Autodesk Fusion 360 part; units mm, degrees
(part 21 of 28)
  line L4025 (139.1545, 85.638) -> (139.2932, 85.4993)
  line L4026 (139.2932, 85.4993) -> (139.4085, 85.3407)
  line L4027 (139.4085, 85.3407) -> (139.4975, 85.1659)
  line L4028 (139.4975, 85.1659) -> (139.5582, 84.9793)
  line L4029 (139.5582, 84.9793) -> (139.5888, 84.7856)
  line L4030 (139.5888, 84.7856) -> (139.5927, 84.6875)
  line L4031 (139.5927, 84.6875) -> (139.5927, 84.1875)
  line L4032 (139.5927, 84.1875) -> (139.5888, 84.0895)
  line L4033 (139.5888, 84.0895) -> (139.5582, 83.8957)
  line L4034 (139.5582, 83.8957) -> (139.4975, 83.7092)
  line L4035 (139.4975, 83.7092) -> (139.4085, 83.5344)
  line L4036 (139.4085, 83.5344) -> (139.2932, 83.3757)
  line L4037 (139.2932, 83.3757) -> (139.1545, 83.237)
  line L4038 (139.1545, 83.237) -> (138.9958, 83.1217)
  line L4039 (138.9958, 83.1217) -> (138.821, 83.0327)
  line L4040 (138.821, 83.0327) -> (138.6345, 82.9721)
  line L4041 (138.6345, 82.9721) -> (138.4408, 82.9414)
  line L4042 (138.4408, 82.9414) -> (138.2446, 82.9414)
  line L4043 (138.2446, 82.9414) -> (138.0509, 82.9721)
  line L4044 (138.0509, 82.9721) -> (137.8643, 83.0327)
  line L4045 (137.8643, 83.0327) -> (137.6896, 83.1217)
  line L4046 (137.6896, 83.1217) -> (137.5309, 83.237)
  line L4047 (137.5309, 83.237) -> (137.3922, 83.3757)
  line L4048 (137.3922, 83.3757) -> (137.2769, 83.5344)
  line L4049 (137.2769, 83.5344) -> (137.1878, 83.7092)
  line L4050 (137.1878, 83.7092) -> (137.1272, 83.8957)
  line L4051 (137.1272, 83.8957) -> (137.0965, 84.0895)
  line L4052 (137.0965, 84.0895) -> (137.0927, 84.1875)
  line L4053 (137.0927, 84.1875) -> (137.0927, 84.6875)
  line L4054 (137.0927, 84.6875) -> (137.0965, 84.7856)
  line L4055 (137.0965, 84.7856) -> (137.1272, 84.9793)
  line L4056 (137.1272, 84.9793) -> (137.1878, 85.1659)
  line L4057 (137.1878, 85.1659) -> (137.2769, 85.3407)
  line L4058 (137.2769, 85.3407) -> (137.3922, 85.4993)
  line L4059 (137.3922, 85.4993) -> (137.5309, 85.638)
  line L4060 (137.5309, 85.638) -> (137.6896, 85.7533)
  line L4061 (137.6896, 85.7533) -> (137.8643, 85.8424)
  line L4062 (137.8643, 85.8424) -> (138.0509, 85.903)
  line L4063 (138.0509, 85.903) -> (138.2446, 85.9337)
  line L4064 (138.2446, 85.9337) -> (138.4408, 85.9337)
  line L4065 (138.4408, 85.9337) -> (138.6345, 85.903)
  line L4066 (24.7524, 89.0733) -> (22.3024, 89.0733)
  line L4067 (22.3024, 89.0733) -> (22.3024, 92.0733)
  line L4068 (22.3024, 92.0733) -> (24.7524, 92.0733)
  line L4069 (24.7524, 92.0733) -> (24.7524, 89.0733)
  line L4070 (59.6774, 89.0733) -> (57.2274, 89.0733)
  line L4071 (57.2274, 89.0733) -> (57.2274, 92.0733)
  line L4072 (57.2274, 92.0733) -> (59.6774, 92.0733)
  line L4073 (59.6774, 92.0733) -> (59.6774, 89.0733)
  line L4074 (94.6024, 89.0733) -> (92.1524, 89.0733)
  line L4075 (92.1524, 89.0733) -> (92.1524, 92.0733)
  line L4076 (92.1524, 92.0733) -> (94.6024, 92.0733)
  line L4077 (94.6024, 92.0733) -> (94.6024, 89.0733)
  line L4078 (129.5274, 89.0733) -> (127.0774, 89.0733)
  line L4079 (127.0774, 89.0733) -> (127.0774, 92.0733)
  line L4080 (127.0774, 92.0733) -> (129.5274, 92.0733)
  line L4081 (129.5274, 92.0733) -> (129.5274, 89.0733)
  line L4082 (21.2733, 92.0395) -> (21.4562, 91.9801)
  line L4083 (21.4562, 91.9801) -> (21.6274, 91.8928)
  line L4084 (21.6274, 91.8928) -> (21.7829, 91.7798)
  line L4085 (21.7829, 91.7798) -> (21.9189, 91.6439)
  line L4086 (21.9189, 91.6439) -> (22.0319, 91.4884)
  line L4087 (22.0319, 91.4884) -> (22.1191, 91.3171)
  line L4088 (22.1191, 91.3171) -> (22.1785, 91.1343)
  line L4089 (22.1785, 91.1343) -> (22.2086, 90.9444)
  line L4090 (22.2086, 90.9444) -> (22.2124, 90.8483)
  line L4091 (22.2124, 90.8483) -> (22.2124, 90.2983)
  line L4092 (22.2124, 90.2983) -> (22.2086, 90.2022)
  line L4093 (22.2086, 90.2022) -> (22.1785, 90.0123)
  line L4094 (22.1785, 90.0123) -> (22.1191, 89.8295)
  line L4095 (22.1191, 89.8295) -> (22.0319, 89.6583)
  line L4096 (22.0319, 89.6583) -> (21.9189, 89.5027)
  line L4097 (21.9189, 89.5027) -> (21.7829, 89.3668)
  line L4098 (21.7829, 89.3668) -> (21.6274, 89.2538)
  line L4099 (21.6274, 89.2538) -> (21.4562, 89.1666)
  line L4100 (21.4562, 89.1666) -> (21.2733, 89.1072)
  line L4101 (21.2733, 89.1072) -> (21.0835, 89.0771)
  line L4102 (21.0835, 89.0771) -> (20.8913, 89.0771)
  line L4103 (20.8913, 89.0771) -> (20.7014, 89.1072)
  line L4104 (20.7014, 89.1072) -> (20.5186, 89.1666)
  line L4105 (20.5186, 89.1666) -> (20.3473, 89.2538)
  line L4106 (20.3473, 89.2538) -> (20.1918, 89.3668)
  line L4107 (20.1918, 89.3668) -> (20.0559, 89.5027)
  line L4108 (20.0559, 89.5027) -> (19.9429, 89.6583)
  line L4109 (19.9429, 89.6583) -> (19.8556, 89.8295)
  line L4110 (19.8556, 89.8295) -> (19.7962, 90.0123)
  line L4111 (19.7962, 90.0123) -> (19.7661, 90.2022)
  line L4112 (19.7661, 90.2022) -> (19.7624, 90.2983)
  line L4113 (19.7624, 90.2983) -> (19.7624, 90.8483)
  line L4114 (19.7624, 90.8483) -> (19.7661, 90.9444)
  line L4115 (19.7661, 90.9444) -> (19.7962, 91.1343)
  line L4116 (19.7962, 91.1343) -> (19.8556, 91.3171)
  line L4117 (19.8556, 91.3171) -> (19.9429, 91.4884)
  line L4118 (19.9429, 91.4884) -> (20.0559, 91.6439)
  line L4119 (20.0559, 91.6439) -> (20.1918, 91.7798)
  line L4120 (20.1918, 91.7798) -> (20.3473, 91.8928)
  line L4121 (20.3473, 91.8928) -> (20.5186, 91.9801)
  line L4122 (20.5186, 91.9801) -> (20.7014, 92.0395)
  line L4123 (20.7014, 92.0395) -> (20.8913, 92.0695)
  line L4124 (20.8913, 92.0695) -> (21.0835, 92.0695)
  line L4125 (21.0835, 92.0695) -> (21.2733, 92.0395)
  line L4126 (56.1983, 92.0395) -> (56.3812, 91.9801)
  line L4127 (56.3812, 91.9801) -> (56.5524, 91.8928)
  line L4128 (56.5524, 91.8928) -> (56.7079, 91.7798)
  line L4129 (56.7079, 91.7798) -> (56.8439, 91.6439)
  line L4130 (56.8439, 91.6439) -> (56.9569, 91.4884)
  line L4131 (56.9569, 91.4884) -> (57.0441, 91.3171)
  line L4132 (57.0441, 91.3171) -> (57.1035, 91.1343)
  line L4133 (57.1035, 91.1343) -> (57.1336, 90.9444)
  line L4134 (57.1336, 90.9444) -> (57.1374, 90.8483)
  line L4135 (57.1374, 90.8483) -> (57.1374, 90.2983)
  line L4136 (57.1374, 90.2983) -> (57.1336, 90.2022)
  line L4137 (57.1336, 90.2022) -> (57.1035, 90.0123)
  line L4138 (57.1035, 90.0123) -> (57.0441, 89.8295)
  line L4139 (57.0441, 89.8295) -> (56.9569, 89.6583)
  line L4140 (56.9569, 89.6583) -> (56.8439, 89.5027)
  line L4141 (56.8439, 89.5027) -> (56.7079, 89.3668)
  line L4142 (56.7079, 89.3668) -> (56.5524, 89.2538)
  line L4143 (56.5524, 89.2538) -> (56.3812, 89.1666)
  line L4144 (56.3812, 89.1666) -> (56.1983, 89.1072)
  line L4145 (56.1983, 89.1072) -> (56.0085, 89.0771)
  line L4146 (56.0085, 89.0771) -> (55.8163, 89.0771)
  line L4147 (55.8163, 89.0771) -> (55.6264, 89.1072)
  line L4148 (55.6264, 89.1072) -> (55.4436, 89.1666)
  line L4149 (55.4436, 89.1666) -> (55.2723, 89.2538)
  line L4150 (55.2723, 89.2538) -> (55.1168, 89.3668)
  line L4151 (55.1168, 89.3668) -> (54.9809, 89.5027)
  line L4152 (54.9809, 89.5027) -> (54.8679, 89.6583)
  line L4153 (54.8679, 89.6583) -> (54.7806, 89.8295)
  line L4154 (54.7806, 89.8295) -> (54.7212, 90.0123)
  line L4155 (54.7212, 90.0123) -> (54.6911, 90.2022)
  line L4156 (54.6911, 90.2022) -> (54.6874, 90.2983)
  line L4157 (54.6874, 90.2983) -> (54.6874, 90.8483)
  line L4158 (54.6874, 90.8483) -> (54.6911, 90.9444)
  line L4159 (54.6911, 90.9444) -> (54.7212, 91.1343)
  line L4160 (54.7212, 91.1343) -> (54.7806, 91.3171)
  line L4161 (54.7806, 91.3171) -> (54.8679, 91.4884)
  line L4162 (54.8679, 91.4884) -> (54.9809, 91.6439)
  line L4163 (54.9809, 91.6439) -> (55.1168, 91.7798)
  line L4164 (55.1168, 91.7798) -> (55.2723, 91.8928)
  line L4165 (55.2723, 91.8928) -> (55.4436, 91.9801)
  line L4166 (55.4436, 91.9801) -> (55.6264, 92.0395)
  line L4167 (55.6264, 92.0395) -> (55.8163, 92.0695)
  line L4168 (55.8163, 92.0695) -> (56.0085, 92.0695)
  line L4169 (56.0085, 92.0695) -> (56.1983, 92.0395)
  line L4170 (91.1233, 92.0395) -> (91.3062, 91.9801)
  line L4171 (91.3062, 91.9801) -> (91.4774, 91.8928)
  line L4172 (91.4774, 91.8928) -> (91.6329, 91.7798)
  line L4173 (91.6329, 91.7798) -> (91.7689, 91.6439)
  line L4174 (91.7689, 91.6439) -> (91.8819, 91.4884)
  line L4175 (91.8819, 91.4884) -> (91.9691, 91.3171)
  line L4176 (91.9691, 91.3171) -> (92.0285, 91.1343)
  line L4177 (92.0285, 91.1343) -> (92.0586, 90.9444)
  line L4178 (92.0586, 90.9444) -> (92.0624, 90.8483)
  line L4179 (92.0624, 90.8483) -> (92.0624, 90.2983)
  line L4180 (92.0624, 90.2983) -> (92.0586, 90.2022)
  line L4181 (92.0586, 90.2022) -> (92.0285, 90.0123)
  line L4182 (92.0285, 90.0123) -> (91.9691, 89.8295)
  line L4183 (91.9691, 89.8295) -> (91.8819, 89.6583)
  line L4184 (91.8819, 89.6583) -> (91.7689, 89.5027)
  line L4185 (91.7689, 89.5027) -> (91.6329, 89.3668)
  line L4186 (91.6329, 89.3668) -> (91.4774, 89.2538)
  line L4187 (91.4774, 89.2538) -> (91.3062, 89.1666)
  line L4188 (91.3062, 89.1666) -> (91.1233, 89.1072)
  line L4189 (91.1233, 89.1072) -> (90.9335, 89.0771)
  line L4190 (90.9335, 89.0771) -> (90.7413, 89.0771)
  line L4191 (90.7413, 89.0771) -> (90.5514, 89.1072)
  line L4192 (90.5514, 89.1072) -> (90.3686, 89.1666)
  line L4193 (90.3686, 89.1666) -> (90.1973, 89.2538)
  line L4194 (90.1973, 89.2538) -> (90.0418, 89.3668)
  line L4195 (90.0418, 89.3668) -> (89.9059, 89.5027)
  line L4196 (89.9059, 89.5027) -> (89.7929, 89.6583)
  line L4197 (89.7929, 89.6583) -> (89.7056, 89.8295)
  line L4198 (89.7056, 89.8295) -> (89.6462, 90.0123)
  line L4199 (89.6462, 90.0123) -> (89.6161, 90.2022)
  line L4200 (89.6161, 90.2022) -> (89.6124, 90.2983)
  line L4201 (89.6124, 90.2983) -> (89.6124, 90.8483)
  line L4202 (89.6124, 90.8483) -> (89.6161, 90.9444)
  line L4203 (89.6161, 90.9444) -> (89.6462, 91.1343)
  line L4204 (89.6462, 91.1343) -> (89.7056, 91.3171)
  line L4205 (89.7056, 91.3171) -> (89.7929, 91.4884)
  line L4206 (89.7929, 91.4884) -> (89.9059, 91.6439)
  line L4207 (89.9059, 91.6439) -> (90.0418, 91.7798)
  line L4208 (90.0418, 91.7798) -> (90.1973, 91.8928)
  line L4209 (90.1973, 91.8928) -> (90.3686, 91.9801)
  line L4210 (90.3686, 91.9801) -> (90.5514, 92.0395)
  line L4211 (90.5514, 92.0395) -> (90.7413, 92.0695)
  line L4212 (90.7413, 92.0695) -> (90.9335, 92.0695)
  line L4213 (90.9335, 92.0695) -> (91.1233, 92.0395)
  line L4214 (126.0483, 92.0395) -> (126.2312, 91.9801)
  line L4215 (126.2312, 91.9801) -> (126.4024, 91.8928)
  line L4216 (126.4024, 91.8928) -> (126.5579, 91.7798)
  line L4217 (126.5579, 91.7798) -> (126.6939, 91.6439)
  line L4218 (126.6939, 91.6439) -> (126.8069, 91.4884)
  line L4219 (126.8069, 91.4884) -> (126.8941, 91.3171)
  line L4220 (126.8941, 91.3171) -> (126.9535, 91.1343)
  line L4221 (126.9535, 91.1343) -> (126.9836, 90.9444)
  line L4222 (126.9836, 90.9444) -> (126.9874, 90.8483)
  line L4223 (126.9874, 90.8483) -> (126.9874, 90.2983)
  line L4224 (126.9874, 90.2983) -> (126.9836, 90.2022)
  line L4225 (126.9836, 90.2022) -> (126.9535, 90.0123)
  line L4226 (126.9535, 90.0123) -> (126.8941, 89.8295)
  line L4227 (126.8941, 89.8295) -> (126.8069, 89.6583)
  line L4228 (126.8069, 89.6583) -> (126.6939, 89.5027)
  line L4229 (126.6939, 89.5027) -> (126.5579, 89.3668)
  line L4230 (126.5579, 89.3668) -> (126.4024, 89.2538)
  line L4231 (126.4024, 89.2538) -> (126.2312, 89.1666)
  line L4232 (126.2312, 89.1666) -> (126.0483, 89.1072)
  line L4233 (126.0483, 89.1072) -> (125.8585, 89.0771)
  line L4234 (125.8585, 89.0771) -> (125.6663, 89.0771)
  line L4235 (125.6663, 89.0771) -> (125.4764, 89.1072)
  line L4236 (125.4764, 89.1072) -> (125.2936, 89.1666)
  line L4237 (125.2936, 89.1666) -> (125.1223, 89.2538)
  line L4238 (125.1223, 89.2538) -> (124.9668, 89.3668)
  line L4239 (124.9668, 89.3668) -> (124.8309, 89.5027)
  line L4240 (124.8309, 89.5027) -> (124.7179, 89.6583)
  line L4241 (124.7179, 89.6583) -> (124.6306, 89.8295)
  line L4242 (124.6306, 89.8295) -> (124.5712, 90.0123)
  line L4243 (124.5712, 90.0123) -> (124.5411, 90.2022)
  line L4244 (124.5411, 90.2022) -> (124.5374, 90.2983)
  line L4245 (124.5374, 90.2983) -> (124.5374, 90.8483)
  line L4246 (124.5374, 90.8483) -> (124.5411, 90.9444)
  line L4247 (124.5411, 90.9444) -> (124.5712, 91.1343)
  line L4248 (124.5712, 91.1343) -> (124.6306, 91.3171)
  line L4249 (124.6306, 91.3171) -> (124.7179, 91.4884)
  line L4250 (124.7179, 91.4884) -> (124.8309, 91.6439)
  line L4251 (124.8309, 91.6439) -> (124.9668, 91.7798)
  line L4252 (124.9668, 91.7798) -> (125.1223, 91.8928)
  line L4253 (125.1223, 91.8928) -> (125.2936, 91.9801)
  line L4254 (125.2936, 91.9801) -> (125.4764, 92.0395)
  line L4255 (125.4764, 92.0395) -> (125.6663, 92.0695)
  line L4256 (125.6663, 92.0695) -> (125.8585, 92.0695)
  line L4257 (125.8585, 92.0695) -> (126.0483, 92.0395)
  line L4258 (33.8595, 93.523) -> (34.046, 93.4624)
  line L4259 (34.046, 93.4624) -> (34.2208, 93.3733)
  line L4260 (34.2208, 93.3733) -> (34.3795, 93.258)
  line L4261 (34.3795, 93.258) -> (34.5182, 93.1193)
  line L4262 (34.5182, 93.1193) -> (34.6335, 92.9607)
  line L4263 (34.6335, 92.9607) -> (34.7225, 92.7859)
  line L4264 (34.7225, 92.7859) -> (34.7832, 92.5993)
  line L4265 (34.7832, 92.5993) -> (34.8138, 92.4056)
  line L4266 (34.8138, 92.4056) -> (34.8177, 92.3075)
  line L4267 (34.8177, 92.3075) -> (34.8177, 91.8075)
  line L4268 (34.8177, 91.8075) -> (34.8138, 91.7095)
  line L4269 (34.8138, 91.7095) -> (34.7832, 91.5157)
  line L4270 (34.7832, 91.5157) -> (34.7225, 91.3292)
  line L4271 (34.7225, 91.3292) -> (34.6335, 91.1544)
  line L4272 (34.6335, 91.1544) -> (34.5182, 90.9957)
  line L4273 (34.5182, 90.9957) -> (34.3795, 90.857)
  line L4274 (34.3795, 90.857) -> (34.2208, 90.7417)
  line L4275 (34.2208, 90.7417) -> (34.046, 90.6527)
  line L4276 (34.046, 90.6527) -> (33.8595, 90.5921)
  line L4277 (33.8595, 90.5921) -> (33.6658, 90.5614)
  line L4278 (33.6658, 90.5614) -> (33.4696, 90.5614)
  line L4279 (33.4696, 90.5614) -> (33.2759, 90.5921)
  line L4280 (33.2759, 90.5921) -> (33.0893, 90.6527)
  line L4281 (33.0893, 90.6527) -> (32.9146, 90.7417)
  line L4282 (32.9146, 90.7417) -> (32.7559, 90.857)
  line L4283 (32.7559, 90.857) -> (32.6172, 90.9957)
  line L4284 (32.6172, 90.9957) -> (32.5019, 91.1544)
  line L4285 (32.5019, 91.1544) -> (32.4128, 91.3292)
  line L4286 (32.4128, 91.3292) -> (32.3522, 91.5157)
  line L4287 (32.3522, 91.5157) -> (32.3215, 91.7095)
  line L4288 (32.3215, 91.7095) -> (32.3177, 91.8075)
  line L4289 (32.3177, 91.8075) -> (32.3177, 92.3075)
  line L4290 (32.3177, 92.3075) -> (32.3215, 92.4056)
  line L4291 (32.3215, 92.4056) -> (32.3522, 92.5993)
  line L4292 (32.3522, 92.5993) -> (32.4128, 92.7859)
  line L4293 (32.4128, 92.7859) -> (32.5019, 92.9607)
  line L4294 (32.5019, 92.9607) -> (32.6172, 93.1193)
  line L4295 (32.6172, 93.1193) -> (32.7559, 93.258)
  line L4296 (32.7559, 93.258) -> (32.9146, 93.3733)
  line L4297 (32.9146, 93.3733) -> (33.0893, 93.4624)
  line L4298 (33.0893, 93.4624) -> (33.2759, 93.523)
  line L4299 (33.2759, 93.523) -> (33.4696, 93.5537)
  line L4300 (33.4696, 93.5537) -> (33.6658, 93.5537)
  line L4301 (33.6658, 93.5537) -> (33.8595, 93.523)
  line L4302 (68.7845, 93.523) -> (68.971, 93.4624)
  line L4303 (68.971, 93.4624) -> (69.1458, 93.3733)
  line L4304 (69.1458, 93.3733) -> (69.3045, 93.258)
  line L4305 (69.3045, 93.258) -> (69.4432, 93.1193)
  line L4306 (69.4432, 93.1193) -> (69.5585, 92.9607)
  line L4307 (69.5585, 92.9607) -> (69.6475, 92.7859)
  line L4308 (69.6475, 92.7859) -> (69.7082, 92.5993)
  line L4309 (69.7082, 92.5993) -> (69.7388, 92.4056)
  line L4310 (69.7388, 92.4056) -> (69.7427, 92.3075)
  line L4311 (69.7427, 92.3075) -> (69.7427, 91.8075)
  line L4312 (69.7427, 91.8075) -> (69.7388, 91.7095)
  line L4313 (69.7388, 91.7095) -> (69.7082, 91.5157)
  line L4314 (69.7082, 91.5157) -> (69.6475, 91.3292)
  line L4315 (69.6475, 91.3292) -> (69.5585, 91.1544)
  line L4316 (69.5585, 91.1544) -> (69.4432, 90.9957)
  line L4317 (69.4432, 90.9957) -> (69.3045, 90.857)
  line L4318 (69.3045, 90.857) -> (69.1458, 90.7417)
  line L4319 (69.1458, 90.7417) -> (68.971, 90.6527)
  line L4320 (68.971, 90.6527) -> (68.7845, 90.5921)
  line L4321 (68.7845, 90.5921) -> (68.5908, 90.5614)
  line L4322 (68.5908, 90.5614) -> (68.3946, 90.5614)
  line L4323 (68.3946, 90.5614) -> (68.2009, 90.5921)
  line L4324 (68.2009, 90.5921) -> (68.0143, 90.6527)
  line L4325 (68.0143, 90.6527) -> (67.8396, 90.7417)
  line L4326 (67.8396, 90.7417) -> (67.6809, 90.857)
  line L4327 (67.6809, 90.857) -> (67.5422, 90.9957)
  line L4328 (67.5422, 90.9957) -> (67.4269, 91.1544)
  line L4329 (67.4269, 91.1544) -> (67.3378, 91.3292)
  line L4330 (67.3378, 91.3292) -> (67.2772, 91.5157)
  line L4331 (67.2772, 91.5157) -> (67.2465, 91.7095)
  line L4332 (67.2465, 91.7095) -> (67.2427, 91.8075)
  line L4333 (67.2427, 91.8075) -> (67.2427, 92.3075)
  line L4334 (67.2427, 92.3075) -> (67.2465, 92.4056)
  line L4335 (67.2465, 92.4056) -> (67.2772, 92.5993)
  line L4336 (67.2772, 92.5993) -> (67.3378, 92.7859)
  line L4337 (67.3378, 92.7859) -> (67.4269, 92.9607)
  line L4338 (67.4269, 92.9607) -> (67.5422, 93.1193)
  line L4339 (67.5422, 93.1193) -> (67.6809, 93.258)
  line L4340 (67.6809, 93.258) -> (67.8396, 93.3733)
  line L4341 (67.8396, 93.3733) -> (68.0143, 93.4624)
  line L4342 (68.0143, 93.4624) -> (68.2009, 93.523)
  line L4343 (68.2009, 93.523) -> (68.3946, 93.5537)
  line L4344 (68.3946, 93.5537) -> (68.5908, 93.5537)
  line L4345 (68.5908, 93.5537) -> (68.7845, 93.523)
  line L4346 (103.7095, 93.523) -> (103.896, 93.4624)
  line L4347 (103.896, 93.4624) -> (104.0708, 93.3733)
  line L4348 (104.0708, 93.3733) -> (104.2295, 93.258)
  line L4349 (104.2295, 93.258) -> (104.3682, 93.1193)
  line L4350 (104.3682, 93.1193) -> (104.4835, 92.9607)
  line L4351 (104.4835, 92.9607) -> (104.5725, 92.7859)
  line L4352 (104.5725, 92.7859) -> (104.6332, 92.5993)
  line L4353 (104.6332, 92.5993) -> (104.6638, 92.4056)
  line L4354 (104.6638, 92.4056) -> (104.6677, 92.3075)
  line L4355 (104.6677, 92.3075) -> (104.6677, 91.8075)
  line L4356 (104.6677, 91.8075) -> (104.6638, 91.7095)
  line L4357 (104.6638, 91.7095) -> (104.6332, 91.5157)
  line L4358 (104.6332, 91.5157) -> (104.5725, 91.3292)
  line L4359 (104.5725, 91.3292) -> (104.4835, 91.1544)
  line L4360 (104.4835, 91.1544) -> (104.3682, 90.9957)
  line L4361 (104.3682, 90.9957) -> (104.2295, 90.857)
  line L4362 (104.2295, 90.857) -> (104.0708, 90.7417)
  line L4363 (104.0708, 90.7417) -> (103.896, 90.6527)
  line L4364 (103.896, 90.6527) -> (103.7095, 90.5921)
  line L4365 (103.7095, 90.5921) -> (103.5158, 90.5614)
  line L4366 (103.5158, 90.5614) -> (103.3196, 90.5614)
  line L4367 (103.3196, 90.5614) -> (103.1259, 90.5921)
  line L4368 (103.1259, 90.5921) -> (102.9393, 90.6527)
  line L4369 (102.9393, 90.6527) -> (102.7646, 90.7417)
  line L4370 (102.7646, 90.7417) -> (102.6059, 90.857)
  line L4371 (102.6059, 90.857) -> (102.4672, 90.9957)
  line L4372 (102.4672, 90.9957) -> (102.3519, 91.1544)
  line L4373 (102.3519, 91.1544) -> (102.2628, 91.3292)
  line L4374 (102.2628, 91.3292) -> (102.2022, 91.5157)
  line L4375 (102.2022, 91.5157) -> (102.1715, 91.7095)
  line L4376 (102.1715, 91.7095) -> (102.1677, 91.8075)
  line L4377 (102.1677, 91.8075) -> (102.1677, 92.3075)
  line L4378 (102.1677, 92.3075) -> (102.1715, 92.4056)
  line L4379 (102.1715, 92.4056) -> (102.2022, 92.5993)
  line L4380 (102.2022, 92.5993) -> (102.2628, 92.7859)
  line L4381 (102.2628, 92.7859) -> (102.3519, 92.9607)
  line L4382 (102.3519, 92.9607) -> (102.4672, 93.1193)
  line L4383 (102.4672, 93.1193) -> (102.6059, 93.258)
  line L4384 (102.6059, 93.258) -> (102.7646, 93.3733)
  line L4385 (102.7646, 93.3733) -> (102.9393, 93.4624)
  line L4386 (102.9393, 93.4624) -> (103.1259, 93.523)
  line L4387 (103.1259, 93.523) -> (103.3196, 93.5537)
  line L4388 (103.3196, 93.5537) -> (103.5158, 93.5537)
  line L4389 (103.5158, 93.5537) -> (103.7095, 93.523)
  line L4390 (138.6345, 93.523) -> (138.821, 93.4624)
  line L4391 (138.821, 93.4624) -> (138.9958, 93.3733)
  line L4392 (138.9958, 93.3733) -> (139.1545, 93.258)
  line L4393 (139.1545, 93.258) -> (139.2932, 93.1193)
  line L4394 (139.2932, 93.1193) -> (139.4085, 92.9607)
  line L4395 (139.4085, 92.9607) -> (139.4975, 92.7859)
  line L4396 (139.4975, 92.7859) -> (139.5582, 92.5993)
  line L4397 (139.5582, 92.5993) -> (139.5888, 92.4056)
  line L4398 (139.5888, 92.4056) -> (139.5927, 92.3075)
  line L4399 (139.5927, 92.3075) -> (139.5927, 91.8075)
  line L4400 (139.5927, 91.8075) -> (139.5888, 91.7095)
  line L4401 (139.5888, 91.7095) -> (139.5582, 91.5157)
  line L4402 (139.5582, 91.5157) -> (139.4975, 91.3292)
  line L4403 (139.4975, 91.3292) -> (139.4085, 91.1544)
  line L4404 (139.4085, 91.1544) -> (139.2932, 90.9957)
  line L4405 (139.2932, 90.9957) -> (139.1545, 90.857)
  line L4406 (139.1545, 90.857) -> (138.9958, 90.7417)
  line L4407 (138.9958, 90.7417) -> (138.821, 90.6527)
  line L4408 (138.821, 90.6527) -> (138.6345, 90.5921)
  line L4409 (138.6345, 90.5921) -> (138.4408, 90.5614)
  line L4410 (138.4408, 90.5614) -> (138.2446, 90.5614)
  line L4411 (138.2446, 90.5614) -> (138.0509, 90.5921)
  line L4412 (138.0509, 90.5921) -> (137.8643, 90.6527)
  line L4413 (137.8643, 90.6527) -> (137.6896, 90.7417)
  line L4414 (137.6896, 90.7417) -> (137.5309, 90.857)
  line L4415 (137.5309, 90.857) -> (137.3922, 90.9957)
  line L4416 (137.3922, 90.9957) -> (137.2769, 91.1544)
  line L4417 (137.2769, 91.1544) -> (137.1878, 91.3292)
  line L4418 (137.1878, 91.3292) -> (137.1272, 91.5157)
  line L4419 (137.1272, 91.5157) -> (137.0965, 91.7095)
  line L4420 (137.0965, 91.7095) -> (137.0927, 91.8075)
  line L4421 (137.0927, 91.8075) -> (137.0927, 92.3075)
  line L4422 (137.0927, 92.3075) -> (137.0965, 92.4056)
  line L4423 (137.0965, 92.4056) -> (137.1272, 92.5993)
  line L4424 (137.1272, 92.5993) -> (137.1878, 92.7859)
  line L4425 (137.1878, 92.7859) -> (137.2769, 92.9607)
  line L4426 (137.2769, 92.9607) -> (137.3922, 93.1193)
  line L4427 (137.3922, 93.1193) -> (137.5309, 93.258)
  line L4428 (137.5309, 93.258) -> (137.6896, 93.3733)
  line L4429 (137.6896, 93.3733) -> (137.8643, 93.4624)
  line L4430 (137.8643, 93.4624) -> (138.0509, 93.523)
  line L4431 (138.0509, 93.523) -> (138.2446, 93.5537)
  line L4432 (138.2446, 93.5537) -> (138.4408, 93.5537)
  line L4433 (138.4408, 93.5537) -> (138.6345, 93.523)
  line L4434 (0.0231, 6.9946) -> (0.025, 6.985)
  line L4435 (0.025, 6.985) -> (0.025, 0.025)
  line L4436 (0.025, 0.025) -> (7.62, 0.025)
  line L4437 (7.62, 0.025) -> (7.6296, 0.0231)
  line L4438 (7.6296, 0.0231) -> (7.6431, 0.0096)
  line L4439 (7.6431, 0.0096) -> (7.6431, -0.0096)
  line L4440 (7.6431, -0.0096) -> (7.6296, -0.0231)
  line L4441 (7.6296, -0.0231) -> (7.62, -0.025)
  line L4442 (7.62, -0.025) -> (0.025, -0.025)
  line L4443 (0.025, -0.025) -> (0.025, -5.08)
  line L4444 (0.025, -5.08) -> (0.0231, -5.0896)
  line L4445 (0.0231, -5.0896) -> (0.0096, -5.1031)
  line L4446 (0.0096, -5.1031) -> (-0.0096, -5.1031)
  line L4447 (-0.0096, -5.1031) -> (-0.0231, -5.0896)
  line L4448 (-0.0231, -5.0896) -> (-0.025, -5.08)
  line L4449 (-0.025, -5.08) -> (-0.025, -0.025)
  line L4450 (-0.025, -0.025) -> (-5.08, -0.025)
  line L4451 (-5.08, -0.025) -> (-5.0896, -0.0231)
  line L4452 (-5.0896, -0.0231) -> (-5.1031, -0.0096)
  line L4453 (-5.1031, -0.0096) -> (-5.1031, 0.0096)
  line L4454 (-5.1031, 0.0096) -> (-5.0896, 0.0231)
  line L4455 (-5.0896, 0.0231) -> (-5.08, 0.025)
  line L4456 (-5.08, 0.025) -> (-0.025, 0.025)
  line L4457 (-0.025, 0.025) -> (-0.025, 6.985)
  line L4458 (-0.025, 6.985) -> (-0.0231, 6.9946)
  line L4459 (-0.0231, 6.9946) -> (-0.0096, 7.0081)
  line L4460 (-0.0096, 7.0081) -> (0.0096, 7.0081)
  line L4461 (0.0096, 7.0081) -> (0.0231, 6.9946)
  line L4462 (66.04, 36.855) -> (66.0496, 36.8531)
  line L4463 (66.0496, 36.8531) -> (66.0631, 36.8396)
  line L4464 (66.0631, 36.8396) -> (66.065, 36.83)
  line L4465 (66.065, 36.83) -> (66.065, 5.08)
  line L4466 (66.065, 5.08) -> (66.0631, 5.0704)
  line L4467 (66.0631, 5.0704) -> (66.0496, 5.0569)
  line L4468 (66.0496, 5.0569) -> (66.04, 5.055)
  line L4469 (66.04, 5.055) -> (8.255, 5.055)
  line L4470 (8.255, 5.055) -> (8.2454, 5.0569)
  line L4471 (8.2454, 5.0569) -> (8.2319, 5.0704)
  line L4472 (8.2319, 5.0704) -> (8.23, 5.08)
  line L4473 (8.23, 5.08) -> (8.23, 36.83)
  line L4474 (8.23, 36.83) -> (8.2319, 36.8396)
  line L4475 (8.2319, 36.8396) -> (8.2454, 36.8531)
  line L4476 (8.2454, 36.8531) -> (8.255, 36.855)
  line L4477 (8.255, 36.855) -> (66.04, 36.855)
  line L4478 (8.28, 36.805) -> (8.28, 5.105)
  line L4479 (8.28, 5.105) -> (66.015, 5.105)
  line L4480 (66.015, 5.105) -> (66.015, 36.805)
  line L4481 (66.015, 36.805) -> (62.865, 36.805)
  line L4482 (62.865, 36.805) -> (8.28, 36.805)
  line L4483 (127, 36.855) -> (127.0096, 36.8531)
  line L4484 (127.0096, 36.8531) -> (127.0231, 36.8396)
  line L4485 (127.0231, 36.8396) -> (127.025, 36.83)
  line L4486 (127.025, 36.83) -> (127.025, 5.08)
  line L4487 (127.025, 5.08) -> (127.0231, 5.0704)
  line L4488 (127.0231, 5.0704) -> (127.0096, 5.0569)
  line L4489 (127.0096, 5.0569) -> (127, 5.055)
  line L4490 (127, 5.055) -> (69.215, 5.055)
  line L4491 (69.215, 5.055) -> (69.2054, 5.0569)
  line L4492 (69.2054, 5.0569) -> (69.1919, 5.0704)
  line L4493 (69.1919, 5.0704) -> (69.19, 5.08)
  line L4494 (69.19, 5.08) -> (69.19, 36.83)
  line L4495 (69.19, 36.83) -> (69.1919, 36.8396)
  line L4496 (69.1919, 36.8396) -> (69.2054, 36.8531)
  line L4497 (69.2054, 36.8531) -> (69.215, 36.855)
  line L4498 (69.215, 36.855) -> (127, 36.855)
  line L4499 (69.24, 36.805) -> (69.24, 5.105)
  line L4500 (69.24, 5.105) -> (126.975, 5.105)
  line L4501 (126.975, 5.105) -> (126.975, 36.805)
  line L4502 (126.975, 36.805) -> (123.825, 36.805)
  line L4503 (123.825, 36.805) -> (69.24, 36.805)
  line L4504 (40.005, 97.815) -> (43.18, 97.815)
  line L4505 (43.18, 97.815) -> (74.93, 97.815)
  line L4506 (74.93, 97.815) -> (74.9396, 97.8131)
  line L4507 (74.9396, 97.8131) -> (74.9531, 97.7996)
  line L4508 (74.9531, 97.7996) -> (74.955, 97.79)
  line L4509 (74.955, 97.79) -> (74.955, 40.005)
  line L4510 (74.955, 40.005) -> (74.9531, 39.9954)
  line L4511 (74.9531, 39.9954) -> (74.9396, 39.9819)
  line L4512 (74.9396, 39.9819) -> (74.93, 39.98)
  line L4513 (74.93, 39.98) -> (43.18, 39.98)
  line L4514 (43.18, 39.98) -> (43.1704, 39.9819)
  line L4515 (43.1704, 39.9819) -> (43.1569, 39.9954)
  line L4516 (43.1569, 39.9954) -> (43.155, 40.005)
  line L4517 (43.155, 40.005) -> (43.155, 97.765)
  line L4518 (43.155, 97.765) -> (40.03, 97.765)
  line L4519 (40.03, 97.765) -> (40.03, 40.005)
  line L4520 (40.03, 40.005) -> (40.0281, 39.9954)
  line L4521 (40.0281, 39.9954) -> (40.0146, 39.9819)
  line L4522 (40.0146, 39.9819) -> (40.005, 39.98)
  line L4523 (40.005, 39.98) -> (8.255, 39.98)
  line L4524 (8.255, 39.98) -> (8.2454, 39.9819)
  line L4525 (8.2454, 39.9819) -> (8.2319, 39.9954)
  line L4526 (8.2319, 39.9954) -> (8.23, 40.005)
  line L4527 (8.23, 40.005) -> (8.23, 97.79)
  line L4528 (8.23, 97.79) -> (8.2319, 97.7996)
  line L4529 (8.2319, 97.7996) -> (8.2454, 97.8131)
  line L4530 (8.2454, 97.8131) -> (8.255, 97.815)
  line L4531 (8.255, 97.815) -> (40.005, 97.815)
  line L4532 (43.205, 97.765) -> (43.205, 40.03)
  line L4533 (43.205, 40.03) -> (74.905, 40.03)
  line L4534 (74.905, 40.03) -> (74.905, 97.765)
  line L4535 (74.905, 97.765) -> (43.205, 97.765)
  line L4536 (8.28, 97.765) -> (8.28, 40.03)
  line L4537 (8.28, 40.03) -> (39.98, 40.03)
  line L4538 (39.98, 40.03) -> (39.98, 97.765)
  line L4539 (39.98, 97.765) -> (8.28, 97.765)
  line L4540 (109.8646, 97.8131) -> (109.8781, 97.7996)
  line L4541 (109.8781, 97.7996) -> (109.88, 97.79)
  line L4542 (109.88, 97.79) -> (109.88, 40.005)
  line L4543 (109.88, 40.005) -> (109.8781, 39.9954)
  line L4544 (109.8781, 39.9954) -> (109.8646, 39.9819)
  line L4545 (109.8646, 39.9819) -> (109.855, 39.98)
  line L4546 (109.855, 39.98) -> (78.105, 39.98)
  line L4547 (78.105, 39.98) -> (78.0954, 39.9819)
  line L4548 (78.0954, 39.9819) -> (78.0819, 39.9954)
  line L4549 (78.0819, 39.9954) -> (78.08, 40.005)
  line L4550 (78.08, 40.005) -> (78.08, 97.79)
  line L4551 (78.08, 97.79) -> (78.0819, 97.7996)
  line L4552 (78.0819, 97.7996) -> (78.0954, 97.8131)
  line L4553 (78.0954, 97.8131) -> (78.105, 97.815)
  line L4554 (78.105, 97.815) -> (109.855, 97.815)
  line L4555 (109.855, 97.815) -> (109.8646, 97.8131)
  line L4556 (78.13, 97.765) -> (78.13, 40.03)
  line L4557 (78.13, 40.03) -> (109.83, 40.03)
  line L4558 (109.83, 40.03) -> (109.83, 97.765)
  line L4559 (109.83, 97.765) -> (78.13, 97.765)
  line L4560 (144.7896, 97.8131) -> (144.8031, 97.7996)
  line L4561 (144.8031, 97.7996) -> (144.805, 97.79)
  line L4562 (144.805, 97.79) -> (144.805, 40.005)
  line L4563 (144.805, 40.005) -> (144.8031, 39.9954)
  line L4564 (144.8031, 39.9954) -> (144.7896, 39.9819)
  line L4565 (144.7896, 39.9819) -> (144.78, 39.98)
  line L4566 (144.78, 39.98) -> (113.03, 39.98)
  line L4567 (113.03, 39.98) -> (113.0204, 39.9819)
  line L4568 (113.0204, 39.9819) -> (113.0069, 39.9954)
  line L4569 (113.0069, 39.9954) -> (113.005, 40.005)
  line L4570 (113.005, 40.005) -> (113.005, 97.79)
  line L4571 (113.005, 97.79) -> (113.0069, 97.7996)
  line L4572 (113.0069, 97.7996) -> (113.0204, 97.8131)
  line L4573 (113.0204, 97.8131) -> (113.03, 97.815)
  line L4574 (113.03, 97.815) -> (144.78, 97.815)
  line L4575 (144.78, 97.815) -> (144.7896, 97.8131)
  line L4576 (113.055, 97.765) -> (113.055, 40.03)
  line L4577 (113.055, 40.03) -> (144.755, 40.03)
  line L4578 (144.755, 40.03) -> (144.755, 97.765)
  line L4579 (144.755, 97.765) -> (113.055, 97.765)
sketch "Blinking Light House-B_Cu (1)" plane through (0, 0, 1.4859) normal (0, 0, 1) x (1, 0, 0)
  line L0 (53.0606, 12.7385, -1.4859) -> (53.2543, 12.7078, -1.4859)
  line L1 (53.2543, 12.7078, -1.4859) -> (53.4409, 12.6472, -1.4859)
  line L2 (53.4409, 12.6472, -1.4859) -> (53.6157, 12.5581, -1.4859)
  line L3 (53.6157, 12.5581, -1.4859) -> (53.7743, 12.4428, -1.4859)
  line L4 (53.7743, 12.4428, -1.4859) -> (53.913, 12.3041, -1.4859)
  line L5 (53.913, 12.3041, -1.4859) -> (54.0283, 12.1454, -1.4859)
  line L6 (54.0283, 12.1454, -1.4859) -> (54.1174, 11.9707, -1.4859)
  line L7 (54.1174, 11.9707, -1.4859) -> (54.178, 11.7841, -1.4859)
  line L8 (54.178, 11.7841, -1.4859) -> (54.2087, 11.5904, -1.4859)
  line L9 (54.2087, 11.5904, -1.4859) -> (54.2087, 11.3942, -1.4859)
  line L10 (54.2087, 11.3942, -1.4859) -> (54.178, 11.2005, -1.4859)
  line L11 (54.178, 11.2005, -1.4859) -> (54.1174, 11.014, -1.4859)
  line L12 (54.1174, 11.014, -1.4859) -> (54.0283, 10.8392, -1.4859)
  line L13 (54.0283, 10.8392, -1.4859) -> (53.913, 10.6805, -1.4859)
  line L14 (53.913, 10.6805, -1.4859) -> (53.7743, 10.5418, -1.4859)
  line L15 (53.7743, 10.5418, -1.4859) -> (53.6157, 10.4265, -1.4859)
  line L16 (53.6157, 10.4265, -1.4859) -> (53.4409, 10.3375, -1.4859)
  line L17 (53.4409, 10.3375, -1.4859) -> (53.2543, 10.2768, -1.4859)
  line L18 (53.2543, 10.2768, -1.4859) -> (53.0606, 10.2462, -1.4859)
  line L19 (53.0606, 10.2462, -1.4859) -> (52.9625, 10.2423, -1.4859)
  line L20 (52.9625, 10.2423, -1.4859) -> (52.4625, 10.2423, -1.4859)
  line L21 (52.4625, 10.2423, -1.4859) -> (52.3645, 10.2462, -1.4859)
  line L22 (52.3645, 10.2462, -1.4859) -> (52.1707, 10.2768, -1.4859)
  line L23 (52.1707, 10.2768, -1.4859) -> (51.9842, 10.3375, -1.4859)
  line L24 (51.9842, 10.3375, -1.4859) -> (51.8094, 10.4265, -1.4859)
  line L25 (51.8094, 10.4265, -1.4859) -> (51.6507, 10.5418, -1.4859)
  line L26 (51.6507, 10.5418, -1.4859) -> (51.512, 10.6805, -1.4859)
  line L27 (51.512, 10.6805, -1.4859) -> (51.3967, 10.8392, -1.4859)
  line L28 (51.3967, 10.8392, -1.4859) -> (51.3077, 11.014, -1.4859)
  line L29 (51.3077, 11.014, -1.4859) -> (51.2471, 11.2005, -1.4859)
  line L30 (51.2471, 11.2005, -1.4859) -> (51.2164, 11.3942, -1.4859)
  line L31 (51.2164, 11.3942, -1.4859) -> (51.2164, 11.5904, -1.4859)
  line L32 (51.2164, 11.5904, -1.4859) -> (51.2471, 11.7841, -1.4859)
  line L33 (51.2471, 11.7841, -1.4859) -> (51.3077, 11.9707, -1.4859)
  line L34 (51.3077, 11.9707, -1.4859) -> (51.3967, 12.1454, -1.4859)
  line L35 (51.3967, 12.1454, -1.4859) -> (51.512, 12.3041, -1.4859)
  line L36 (51.512, 12.3041, -1.4859) -> (51.6507, 12.4428, -1.4859)
  line L37 (51.6507, 12.4428, -1.4859) -> (51.8094, 12.5581, -1.4859)
  line L38 (51.8094, 12.5581, -1.4859) -> (51.9842, 12.6472, -1.4859)
  line L39 (51.9842, 12.6472, -1.4859) -> (52.1707, 12.7078, -1.4859)
  line L40 (52.1707, 12.7078, -1.4859) -> (52.3645, 12.7385, -1.4859)
  line L41 (52.3645, 12.7385, -1.4859) -> (52.4625, 12.7423, -1.4859)
  line L42 (52.4625, 12.7423, -1.4859) -> (52.9625, 12.7423, -1.4859)
  line L43 (52.9625, 12.7423, -1.4859) -> (53.0606, 12.7385, -1.4859)
  line L44 (60.6806, 12.7385, -1.4859) -> (60.8743, 12.7078, -1.4859)
  line L45 (60.8743, 12.7078, -1.4859) -> (61.0609, 12.6472, -1.4859)
  line L46 (61.0609, 12.6472, -1.4859) -> (61.2357, 12.5581, -1.4859)
  line L47 (61.2357, 12.5581, -1.4859) -> (61.3943, 12.4428, -1.4859)
  line L48 (61.3943, 12.4428, -1.4859) -> (61.533, 12.3041, -1.4859)
  line L49 (61.533, 12.3041, -1.4859) -> (61.6483, 12.1454, -1.4859)
  line L50 (61.6483, 12.1454, -1.4859) -> (61.7374, 11.9707, -1.4859)
  line L51 (61.7374, 11.9707, -1.4859) -> (61.798, 11.7841, -1.4859)
  line L52 (61.798, 11.7841, -1.4859) -> (61.8287, 11.5904, -1.4859)
  line L53 (61.8287, 11.5904, -1.4859) -> (61.8287, 11.3942, -1.4859)
  line L54 (61.8287, 11.3942, -1.4859) -> (61.798, 11.2005, -1.4859)
  line L55 (61.798, 11.2005, -1.4859) -> (61.7374, 11.014, -1.4859)
  line L56 (61.7374, 11.014, -1.4859) -> (61.6483, 10.8392, -1.4859)
  line L57 (61.6483, 10.8392, -1.4859) -> (61.533, 10.6805, -1.4859)
  line L58 (61.533, 10.6805, -1.4859) -> (61.3943, 10.5418, -1.4859)
  line L59 (61.3943, 10.5418, -1.4859) -> (61.2357, 10.4265, -1.4859)
  line L60 (61.2357, 10.4265, -1.4859) -> (61.0609, 10.3375, -1.4859)
  line L61 (61.0609, 10.3375, -1.4859) -> (60.8743, 10.2768, -1.4859)
  line L62 (60.8743, 10.2768, -1.4859) -> (60.6806, 10.2462, -1.4859)
  line L63 (60.6806, 10.2462, -1.4859) -> (60.5825, 10.2423, -1.4859)
  line L64 (60.5825, 10.2423, -1.4859) -> (60.0825, 10.2423, -1.4859)
  line L65 (60.0825, 10.2423, -1.4859) -> (59.9845, 10.2462, -1.4859)
  line L66 (59.9845, 10.2462, -1.4859) -> (59.7907, 10.2768, -1.4859)
  line L67 (59.7907, 10.2768, -1.4859) -> (59.6042, 10.3375, -1.4859)
  line L68 (59.6042, 10.3375, -1.4859) -> (59.4294, 10.4265, -1.4859)
  line L69 (59.4294, 10.4265, -1.4859) -> (59.2707, 10.5418, -1.4859)
  line L70 (59.2707, 10.5418, -1.4859) -> (59.132, 10.6805, -1.4859)
  line L71 (59.132, 10.6805, -1.4859) -> (59.0167, 10.8392, -1.4859)
  line L72 (59.0167, 10.8392, -1.4859) -> (58.9277, 11.014, -1.4859)
  line L73 (58.9277, 11.014, -1.4859) -> (58.8671, 11.2005, -1.4859)
  line L74 (58.8671, 11.2005, -1.4859) -> (58.8364, 11.3942, -1.4859)
  line L75 (58.8364, 11.3942, -1.4859) -> (58.8364, 11.5904, -1.4859)
  line L76 (58.8364, 11.5904, -1.4859) -> (58.8671, 11.7841, -1.4859)
  line L77 (58.8671, 11.7841, -1.4859) -> (58.9277, 11.9707, -1.4859)
  line L78 (58.9277, 11.9707, -1.4859) -> (59.0167, 12.1454, -1.4859)
  line L79 (59.0167, 12.1454, -1.4859) -> (59.132, 12.3041, -1.4859)
  line L80 (59.132, 12.3041, -1.4859) -> (59.2707, 12.4428, -1.4859)
  line L81 (59.2707, 12.4428, -1.4859) -> (59.4294, 12.5581, -1.4859)
  line L82 (59.4294, 12.5581, -1.4859) -> (59.6042, 12.6472, -1.4859)
  line L83 (59.6042, 12.6472, -1.4859) -> (59.7907, 12.7078, -1.4859)
  line L84 (59.7907, 12.7078, -1.4859) -> (59.9845, 12.7385, -1.4859)
  line L85 (59.9845, 12.7385, -1.4859) -> (60.0825, 12.7423, -1.4859)
  line L86 (60.0825, 12.7423, -1.4859) -> (60.5825, 12.7423, -1.4859)
  line L87 (60.5825, 12.7423, -1.4859) -> (60.6806, 12.7385, -1.4859)
  line L88 (114.0206, 12.7385, -1.4859) -> (114.2143, 12.7078, -1.4859)
  line L89 (114.2143, 12.7078, -1.4859) -> (114.4009, 12.6472, -1.4859)
  line L90 (114.4009, 12.6472, -1.4859) -> (114.5757, 12.5581, -1.4859)
  line L91 (114.5757, 12.5581, -1.4859) -> (114.7343, 12.4428, -1.4859)
  line L92 (114.7343, 12.4428, -1.4859) -> (114.873, 12.3041, -1.4859)
  line L93 (114.873, 12.3041, -1.4859) -> (114.9883, 12.1454, -1.4859)
  line L94 (114.9883, 12.1454, -1.4859) -> (115.0774, 11.9707, -1.4859)
  line L95 (115.0774, 11.9707, -1.4859) -> (115.138, 11.7841, -1.4859)
  line L96 (115.138, 11.7841, -1.4859) -> (115.1687, 11.5904, -1.4859)
  line L97 (115.1687, 11.5904, -1.4859) -> (115.1687, 11.3942, -1.4859)
  line L98 (115.1687, 11.3942, -1.4859) -> (115.138, 11.2005, -1.4859)
  line L99 (115.138, 11.2005, -1.4859) -> (115.0774, 11.014, -1.4859)
  line L100 (115.0774, 11.014, -1.4859) -> (114.9883, 10.8392, -1.4859)
  line L101 (114.9883, 10.8392, -1.4859) -> (114.873, 10.6805, -1.4859)
  line L102 (114.873, 10.6805, -1.4859) -> (114.7343, 10.5418, -1.4859)
  line L103 (114.7343, 10.5418, -1.4859) -> (114.5757, 10.4265, -1.4859)
  line L104 (114.5757, 10.4265, -1.4859) -> (114.4009, 10.3375, -1.4859)
  line L105 (114.4009, 10.3375, -1.4859) -> (114.2143, 10.2768, -1.4859)
  line L106 (114.2143, 10.2768, -1.4859) -> (114.0206, 10.2462, -1.4859)
  line L107 (114.0206, 10.2462, -1.4859) -> (113.9225, 10.2423, -1.4859)
  line L108 (113.9225, 10.2423, -1.4859) -> (113.4225, 10.2423, -1.4859)
  line L109 (113.4225, 10.2423, -1.4859) -> (113.3245, 10.2462, -1.4859)
  line L110 (113.3245, 10.2462, -1.4859) -> (113.1307, 10.2768, -1.4859)
  line L111 (113.1307, 10.2768, -1.4859) -> (112.9442, 10.3375, -1.4859)
  line L112 (112.9442, 10.3375, -1.4859) -> (112.7694, 10.4265, -1.4859)
  line L113 (112.7694, 10.4265, -1.4859) -> (112.6107, 10.5418, -1.4859)
  line L114 (112.6107, 10.5418, -1.4859) -> (112.472, 10.6805, -1.4859)
  line L115 (112.472, 10.6805, -1.4859) -> (112.3567, 10.8392, -1.4859)
  line L116 (112.3567, 10.8392, -1.4859) -> (112.2677, 11.014, -1.4859)
  line L117 (112.2677, 11.014, -1.4859) -> (112.2071, 11.2005, -1.4859)
  line L118 (112.2071, 11.2005, -1.4859) -> (112.1764, 11.3942, -1.4859)
  line L119 (112.1764, 11.3942, -1.4859) -> (112.1764, 11.5904, -1.4859)
  line L120 (112.1764, 11.5904, -1.4859) -> (112.2071, 11.7841, -1.4859)
  line L121 (112.2071, 11.7841, -1.4859) -> (112.2677, 11.9707, -1.4859)
  line L122 (112.2677, 11.9707, -1.4859) -> (112.3567, 12.1454, -1.4859)
  line L123 (112.3567, 12.1454, -1.4859) -> (112.472, 12.3041, -1.4859)
  line L124 (112.472, 12.3041, -1.4859) -> (112.6107, 12.4428, -1.4859)
  line L125 (112.6107, 12.4428, -1.4859) -> (112.7694, 12.5581, -1.4859)
  line L126 (112.7694, 12.5581, -1.4859) -> (112.9442, 12.6472, -1.4859)
  line L127 (112.9442, 12.6472, -1.4859) -> (113.1307, 12.7078, -1.4859)
  line L128 (113.1307, 12.7078, -1.4859) -> (113.3245, 12.7385, -1.4859)
  line L129 (113.3245, 12.7385, -1.4859) -> (113.4225, 12.7423, -1.4859)
  line L130 (113.4225, 12.7423, -1.4859) -> (113.9225, 12.7423, -1.4859)
  line L131 (113.9225, 12.7423, -1.4859) -> (114.0206, 12.7385, -1.4859)
  line L132 (121.6406, 12.7385, -1.4859) -> (121.8343, 12.7078, -1.4859)
  line L133 (121.8343, 12.7078, -1.4859) -> (122.0209, 12.6472, -1.4859)
  line L134 (122.0209, 12.6472, -1.4859) -> (122.1957, 12.5581, -1.4859)
  line L135 (122.1957, 12.5581, -1.4859) -> (122.3543, 12.4428, -1.4859)
  line L136 (122.3543, 12.4428, -1.4859) -> (122.493, 12.3041, -1.4859)
  line L137 (122.493, 12.3041, -1.4859) -> (122.6083, 12.1454, -1.4859)
  line L138 (122.6083, 12.1454, -1.4859) -> (122.6974, 11.9707, -1.4859)
  line L139 (122.6974, 11.9707, -1.4859) -> (122.758, 11.7841, -1.4859)
  line L140 (122.758, 11.7841, -1.4859) -> (122.7887, 11.5904, -1.4859)
  line L141 (122.7887, 11.5904, -1.4859) -> (122.7887, 11.3942, -1.4859)
  line L142 (122.7887, 11.3942, -1.4859) -> (122.758, 11.2005, -1.4859)
  line L143 (122.758, 11.2005, -1.4859) -> (122.6974, 11.014, -1.4859)
  line L144 (122.6974, 11.014, -1.4859) -> (122.6083, 10.8392, -1.4859)
  line L145 (122.6083, 10.8392, -1.4859) -> (122.493, 10.6805, -1.4859)
  line L146 (122.493, 10.6805, -1.4859) -> (122.3543, 10.5418, -1.4859)
  line L147 (122.3543, 10.5418, -1.4859) -> (122.1957, 10.4265, -1.4859)
  line L148 (122.1957, 10.4265, -1.4859) -> (122.0209, 10.3375, -1.4859)
  line L149 (122.0209, 10.3375, -1.4859) -> (121.8343, 10.2768, -1.4859)
  line L150 (121.8343, 10.2768, -1.4859) -> (121.6406, 10.2462, -1.4859)
  line L151 (121.6406, 10.2462, -1.4859) -> (121.5425, 10.2423, -1.4859)
  line L152 (121.5425, 10.2423, -1.4859) -> (121.0425, 10.2423, -1.4859)
  line L153 (121.0425, 10.2423, -1.4859) -> (120.9445, 10.2462, -1.4859)
  line L154 (120.9445, 10.2462, -1.4859) -> (120.7507, 10.2768, -1.4859)
  line L155 (120.7507, 10.2768, -1.4859) -> (120.5642, 10.3375, -1.4859)
  line L156 (120.5642, 10.3375, -1.4859) -> (120.3894, 10.4265, -1.4859)
  line L157 (120.3894, 10.4265, -1.4859) -> (120.2307, 10.5418, -1.4859)
  line L158 (120.2307, 10.5418, -1.4859) -> (120.092, 10.6805, -1.4859)
  line L159 (120.092, 10.6805, -1.4859) -> (119.9767, 10.8392, -1.4859)
  line L160 (119.9767, 10.8392, -1.4859) -> (119.8877, 11.014, -1.4859)
  line L161 (119.8877, 11.014, -1.4859) -> (119.8271, 11.2005, -1.4859)
  line L162 (119.8271, 11.2005, -1.4859) -> (119.7964, 11.3942, -1.4859)
  line L163 (119.7964, 11.3942, -1.4859) -> (119.7964, 11.5904, -1.4859)
  line L164 (119.7964, 11.5904, -1.4859) -> (119.8271, 11.7841, -1.4859)
  line L165 (119.8271, 11.7841, -1.4859) -> (119.8877, 11.9707, -1.4859)
  line L166 (119.8877, 11.9707, -1.4859) -> (119.9767, 12.1454, -1.4859)
  line L167 (119.9767, 12.1454, -1.4859) -> (120.092, 12.3041, -1.4859)
  line L168 (120.092, 12.3041, -1.4859) -> (120.2307, 12.4428, -1.4859)
  line L169 (120.2307, 12.4428, -1.4859) -> (120.3894, 12.5581, -1.4859)
  line L170 (120.3894, 12.5581, -1.4859) -> (120.5642, 12.6472, -1.4859)
  line L171 (120.5642, 12.6472, -1.4859) -> (120.7507, 12.7078, -1.4859)
  line L172 (120.7507, 12.7078, -1.4859) -> (120.9445, 12.7385, -1.4859)
  line L173 (120.9445, 12.7385, -1.4859) -> (121.0425, 12.7423, -1.4859)
  line L174 (121.0425, 12.7423, -1.4859) -> (121.5425, 12.7423, -1.4859)
  line L175 (121.5425, 12.7423, -1.4859) -> (121.6406, 12.7385, -1.4859)
  line L176 (29.7148, 13.5881, -1.4859) -> (29.9085, 13.5574, -1.4859)
  line L177 (29.9085, 13.5574, -1.4859) -> (30.0951, 13.4968, -1.4859)
  line L178 (30.0951, 13.4968, -1.4859) -> (30.2699, 13.4078, -1.4859)
  line L179 (30.2699, 13.4078, -1.4859) -> (30.4286, 13.2925, -1.4859)
  line L180 (30.4286, 13.2925, -1.4859) -> (30.5672, 13.1538, -1.4859)
  line L181 (30.5672, 13.1538, -1.4859) -> (30.6825, 12.9951, -1.4859)
  line L182 (30.6825, 12.9951, -1.4859) -> (30.7716, 12.8203, -1.4859)
  line L183 (30.7716, 12.8203, -1.4859) -> (30.8322, 12.6338, -1.4859)
  line L184 (30.8322, 12.6338, -1.4859) -> (30.8629, 12.44, -1.4859)
  line L185 (30.8629, 12.44, -1.4859) -> (30.8629, 12.2439, -1.4859)
  line L186 (30.8629, 12.2439, -1.4859) -> (30.8322, 12.0501, -1.4859)
  line L187 (30.8322, 12.0501, -1.4859) -> (30.7716, 11.8636, -1.4859)
  line L188 (30.7716, 11.8636, -1.4859) -> (30.6825, 11.6888, -1.4859)
  line L189 (30.6825, 11.6888, -1.4859) -> (30.5672, 11.5301, -1.4859)
  line L190 (30.5672, 11.5301, -1.4859) -> (30.4286, 11.3914, -1.4859)
  line L191 (30.4286, 11.3914, -1.4859) -> (30.2699, 11.2762, -1.4859)
  line L192 (30.2699, 11.2762, -1.4859) -> (30.0951, 11.1871, -1.4859)
  line L193 (30.0951, 11.1871, -1.4859) -> (29.9085, 11.1265, -1.4859)
  line L194 (29.9085, 11.1265, -1.4859) -> (29.7148, 11.0958, -1.4859)
  line L195 (29.7148, 11.0958, -1.4859) -> (29.6167, 11.092, -1.4859)
  line L196 (29.6167, 11.092, -1.4859) -> (29.1167, 11.092, -1.4859)
  line L197 (29.1167, 11.092, -1.4859) -> (29.0187, 11.0958, -1.4859)
  line L198 (29.0187, 11.0958, -1.4859) -> (28.8249, 11.1265, -1.4859)
  line L199 (28.8249, 11.1265, -1.4859) -> (28.6384, 11.1871, -1.4859)
  line L200 (28.6384, 11.1871, -1.4859) -> (28.4636, 11.2762, -1.4859)
  line L201 (28.4636, 11.2762, -1.4859) -> (28.3049, 11.3915, -1.4859)
  line L202 (28.3049, 11.3915, -1.4859) -> (28.1662, 11.5301, -1.4859)
  line L203 (28.1662, 11.5301, -1.4859) -> (28.0509, 11.6888, -1.4859)
  line L204 (28.0509, 11.6888, -1.4859) -> (27.9619, 11.8636, -1.4859)
  line L205 (27.9619, 11.8636, -1.4859) -> (27.9013, 12.0501, -1.4859)
  line L206 (27.9013, 12.0501, -1.4859) -> (27.8706, 12.2439, -1.4859)
  line L207 (27.8706, 12.2439, -1.4859) -> (27.8706, 12.44, -1.4859)
  line L208 (27.8706, 12.44, -1.4859) -> (27.9013, 12.6338, -1.4859)
  line L209 (27.9013, 12.6338, -1.4859) -> (27.9619, 12.8203, -1.4859)
  line L210 (27.9619, 12.8203, -1.4859) -> (28.0509, 12.9951, -1.4859)
  line L211 (28.0509, 12.9951, -1.4859) -> (28.1662, 13.1538, -1.4859)
  line L212 (28.1662, 13.1538, -1.4859) -> (28.3049, 13.2925, -1.4859)
  line L213 (28.3049, 13.2925, -1.4859) -> (28.4636, 13.4078, -1.4859)
  line L214 (28.4636, 13.4078, -1.4859) -> (28.6384, 13.4968, -1.4859)
  line L215 (28.6384, 13.4968, -1.4859) -> (28.8249, 13.5574, -1.4859)
  line L216 (28.8249, 13.5574, -1.4859) -> (29.0187, 13.5881, -1.4859)
  line L217 (29.0187, 13.5881, -1.4859) -> (29.1167, 13.592, -1.4859)
  line L218 (29.1167, 13.592, -1.4859) -> (29.6167, 13.592, -1.4859)
  line L219 (29.6167, 13.592, -1.4859) -> (29.7148, 13.5881, -1.4859)
  line L220 (37.3348, 13.5881, -1.4859) -> (37.5285, 13.5574, -1.4859)
  line L221 (37.5285, 13.5574, -1.4859) -> (37.7151, 13.4968, -1.4859)
  line L222 (37.7151, 13.4968, -1.4859) -> (37.8899, 13.4078, -1.4859)
  line L223 (37.8899, 13.4078, -1.4859) -> (38.0485, 13.2925, -1.4859)
  line L224 (38.0486, 13.2925, -1.4859) -> (38.1872, 13.1538, -1.4859)
  line L225 (38.1872, 13.1538, -1.4859) -> (38.3025, 12.9951, -1.4859)
  line L226 (38.3025, 12.9951, -1.4859) -> (38.3916, 12.8203, -1.4859)
  line L227 (38.3916, 12.8203, -1.4859) -> (38.4522, 12.6338, -1.4859)
  line L228 (38.4522, 12.6338, -1.4859) -> (38.4829, 12.44, -1.4859)
  line L229 (38.4829, 12.44, -1.4859) -> (38.4829, 12.2439, -1.4859)
  line L230 (38.4829, 12.2439, -1.4859) -> (38.4522, 12.0501, -1.4859)
  line L231 (38.4522, 12.0501, -1.4859) -> (38.3916, 11.8636, -1.4859)
  line L232 (38.3916, 11.8636, -1.4859) -> (38.3025, 11.6888, -1.4859)
  line L233 (38.3025, 11.6888, -1.4859) -> (38.1872, 11.5301, -1.4859)
  line L234 (38.1872, 11.5301, -1.4859) -> (38.0486, 11.3914, -1.4859)
  line L235 (38.0486, 11.3914, -1.4859) -> (37.8899, 11.2762, -1.4859)
  line L236 (37.8899, 11.2762, -1.4859) -> (37.7151, 11.1871, -1.4859)
  line L237 (37.7151, 11.1871, -1.4859) -> (37.5285, 11.1265, -1.4859)
  line L238 (37.5285, 11.1265, -1.4859) -> (37.3348, 11.0958, -1.4859)
  line L239 (37.3348, 11.0958, -1.4859) -> (37.2367, 11.092, -1.4859)
  line L240 (37.2367, 11.092, -1.4859) -> (36.7367, 11.092, -1.4859)
  line L241 (36.7367, 11.092, -1.4859) -> (36.6387, 11.0958, -1.4859)
  line L242 (36.6387, 11.0958, -1.4859) -> (36.4449, 11.1265, -1.4859)
  line L243 (36.4449, 11.1265, -1.4859) -> (36.2584, 11.1871, -1.4859)
  line L244 (36.2584, 11.1871, -1.4859) -> (36.0836, 11.2762, -1.4859)
  line L245 (36.0836, 11.2762, -1.4859) -> (35.9249, 11.3915, -1.4859)
  line L246 (35.9249, 11.3915, -1.4859) -> (35.7862, 11.5301, -1.4859)
  line L247 (35.7862, 11.5301, -1.4859) -> (35.6709, 11.6888, -1.4859)
  line L248 (35.6709, 11.6888, -1.4859) -> (35.5819, 11.8636, -1.4859)
  line L249 (35.5819, 11.8636, -1.4859) -> (35.5213, 12.0501, -1.4859)
  line L250 (35.5213, 12.0501, -1.4859) -> (35.4906, 12.2439, -1.4859)
  line L251 (35.4906, 12.2439, -1.4859) -> (35.4906, 12.44, -1.4859)
  line L252 (35.4906, 12.44, -1.4859) -> (35.5213, 12.6338, -1.4859)
  line L253 (35.5213, 12.6338, -1.4859) -> (35.5819, 12.8203, -1.4859)
  line L254 (35.5819, 12.8203, -1.4859) -> (35.6709, 12.9951, -1.4859)
  line L255 (35.6709, 12.9951, -1.4859) -> (35.7862, 13.1538, -1.4859)
  line L256 (35.7862, 13.1538, -1.4859) -> (35.9249, 13.2925, -1.4859)
  line L257 (35.9249, 13.2925, -1.4859) -> (36.0836, 13.4078, -1.4859)
  line L258 (36.0836, 13.4078, -1.4859) -> (36.2584, 13.4968, -1.4859)
  line L259 (36.2584, 13.4968, -1.4859) -> (36.4449, 13.5574, -1.4859)
  line L260 (36.4449, 13.5574, -1.4859) -> (36.6387, 13.5881, -1.4859)
  line L261 (36.6387, 13.5881, -1.4859) -> (36.7367, 13.592, -1.4859)
  line L262 (36.7367, 13.592, -1.4859) -> (37.2367, 13.592, -1.4859)
  line L263 (37.2367, 13.592, -1.4859) -> (37.3348, 13.5881, -1.4859)
  line L264 (90.6748, 13.5881, -1.4859) -> (90.8685, 13.5574, -1.4859)
  line L265 (90.8685, 13.5574, -1.4859) -> (91.0551, 13.4968, -1.4859)
  line L266 (91.0551, 13.4968, -1.4859) -> (91.2299, 13.4078, -1.4859)
  line L267 (91.2299, 13.4078, -1.4859) -> (91.3885, 13.2925, -1.4859)
  line L268 (91.3885, 13.2925, -1.4859) -> (91.5272, 13.1538, -1.4859)
  line L269 (91.5272, 13.1538, -1.4859) -> (91.6425, 12.9951, -1.4859)
  line L270 (91.6425, 12.9951, -1.4859) -> (91.7316, 12.8203, -1.4859)
  line L271 (91.7316, 12.8203, -1.4859) -> (91.7922, 12.6338, -1.4859)
  line L272 (91.7922, 12.6338, -1.4859) -> (91.8229, 12.44, -1.4859)
  line L273 (91.8229, 12.44, -1.4859) -> (91.8229, 12.2439, -1.4859)
  line L274 (91.8229, 12.2439, -1.4859) -> (91.7922, 12.0501, -1.4859)
  line L275 (91.7922, 12.0501, -1.4859) -> (91.7316, 11.8636, -1.4859)
  line L276 (91.7316, 11.8636, -1.4859) -> (91.6425, 11.6888, -1.4859)
  line L277 (91.6425, 11.6888, -1.4859) -> (91.5272, 11.5301, -1.4859)
  line L278 (91.5272, 11.5301, -1.4859) -> (91.3885, 11.3914, -1.4859)
  line L279 (91.3885, 11.3914, -1.4859) -> (91.2299, 11.2762, -1.4859)
  line L280 (91.2299, 11.2762, -1.4859) -> (91.0551, 11.1871, -1.4859)
  line L281 (91.0551, 11.1871, -1.4859) -> (90.8685, 11.1265, -1.4859)
  line L282 (90.8685, 11.1265, -1.4859) -> (90.6748, 11.0958, -1.4859)